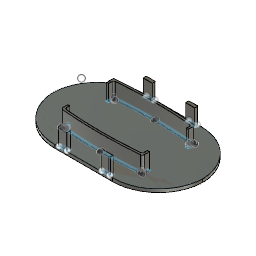
astra-sdr-spacer (Autodesk Fusion 360 design; units mm, degrees)
part number: 2026-04-11-15-15-42-801
Autodesk Fusion 360 part; units mm, degrees
sketch "Sketch1" plane through (0, 0, 0) normal (0, 0, 1) x (1, 0, 0)
  line L0 (70, 0) -> (158, 0)
  line L1 (228, 70) -> (228, 65)
  line L2 (158, 135) -> (70, 135)
  line L3 (0, 65) -> (0, 70)
  arc A0 (70, 135) -> (0, 65) centre (70, 65) ccw
  arc A1 (228, 65) -> (158, 135) centre (158, 65) ccw
  arc A2 (0, 70) -> (70, 0) centre (70, 70) ccw
  arc A3 (158, 0) -> (228, 70) centre (158, 70) ccw
  point P0 (228, 0)
  point P1 (0, 135)
  dimension "d1" = 135
  dimension "d2" = 228
  dimension "d3" = 70
  dimension "d4" = 70
  dimension "d5" = 70
  dimension "d6" = 70
  constraint horizontal L0
  constraint vertical L1
  constraint horizontal L2
  constraint vertical L3
  constraint coincident P1 L2
  constraint coincident P1 L3
  constraint tangent L2 A0
  constraint tangent L3 A0
  constraint tangent L1 A1
  constraint tangent L2 A1
  constraint coincident origin L0
  constraint coincident origin L3
  constraint tangent L0 A2
  constraint tangent L3 A2
  constraint coincident P0 L0
  constraint coincident P0 L1
  constraint tangent L0 A3
  constraint tangent L1 A3
  measures "d1" distance of origin P1
  measures "d2" distance of origin P0
  measures "d3" radius of A0
  measures "d4" radius of A1
  measures "d5" radius of A2
  measures "d6" radius of A3
extrude "Extrude1" add sketch "Sketch1" along normal blind 5 contours L0 L2 A0 A1 A2 A3
sketch "Sketch2" plane through (0, 0, 5) normal (0, 0, 1) x (-1, 0, 0)
  arc A0 (-158, 0) -> (-227.9553, -67.5) centre (-158, -70) ccw
  arc A1 (-227.9553, -67.5) -> (-158, -135) centre (-158, -65) ccw
  line L0 (-158, -135) -> (-70, -135)
  arc A2 (-70, -135) -> (-0.0447, -67.5) centre (-70, -65) ccw
  arc A3 (-0.0447, -67.5) -> (-70, 0) centre (-70, -70) ccw
  line L1 (-70, 0) -> (-158, 0)
  line L2 (-75.5447, -135.011) -> (-87.5447, -135.011)
  line L3 (-88.5447, -134.011) -> (-88.5447, -130.011)
  line L4 (-88.5447, -130.011) -> (-74.5447, -130.011)
  line L5 (-74.5447, -130.011) -> (-74.5447, -134.011)
  line L6 (-152.4553, -134.8199) -> (-140.4553, -134.8199)
  line L7 (-139.4553, -133.8199) -> (-139.4553, -129.8199)
  line L8 (-139.4553, -129.8199) -> (-153.4553, -129.8199)
  line L9 (-153.4553, -129.8199) -> (-153.4553, -133.8199)
  arc A4 (-75.5447, -135.011) -> (-74.5447, -134.011) centre (-75.5447, -134.011) ccw
  arc A5 (-88.5447, -134.011) -> (-87.5447, -135.011) centre (-87.5447, -134.011) ccw
  arc A6 (-140.4553, -134.8199) -> (-139.4553, -133.8199) centre (-140.4553, -133.8199) ccw
  arc A7 (-153.4553, -133.8199) -> (-152.4553, -134.8199) centre (-152.4553, -133.8199) ccw
  line L10 (-152.4553, 0) -> (-140.4553, 0)
  line L11 (-139.1553, -1.3) -> (-139.1553, -5)
  line L12 (-139.1553, -5) -> (-153.7553, -5)
  line L13 (-153.7553, -5) -> (-153.7553, -1.3)
  line L14 (-75.5447, 0) -> (-87.5447, 0)
  line L15 (-88.8447, -1.3) -> (-88.8447, -5)
  line L16 (-88.8447, -5) -> (-74.2447, -5)
  line L17 (-74.2447, -5) -> (-74.2447, -1.3)
  arc A8 (-152.4553, 0) -> (-153.7553, -1.3) centre (-152.4553, -1.3) ccw
  arc A9 (-139.1553, -1.3) -> (-140.4553, 0) centre (-140.4553, -1.3) ccw
  arc A10 (-87.5447, 0) -> (-88.8447, -1.3) centre (-87.5447, -1.3) ccw
  arc A11 (-74.2447, -1.3) -> (-75.5447, 0) centre (-75.5447, -1.3) ccw
  dimension "d9" = 1
  dimension "d10" = 1.3
  dimension "d90" = 75.5
  dimension "d91" = 75.5
  dimension "d92" = 75.5
  dimension "d93" = 75.5
  dimension "d94" = 12
  dimension "d95" = 12
  dimension "d96" = 12
  dimension "d97" = 12
  constraint horizontal L2
  constraint vertical L3
  constraint horizontal L4
  constraint vertical L5
  constraint horizontal L6
  constraint vertical L7
  constraint horizontal L8
  constraint vertical L9
  constraint tangent L2 A4
  constraint tangent L5 A4
  constraint tangent L2 A5
  constraint tangent L3 A5
  constraint equal A4 A5
  constraint tangent L6 A6
  constraint tangent L7 A6
  constraint equal A4 A6
  constraint tangent L6 A7
  constraint tangent L9 A7
  constraint equal A4 A7
  constraint horizontal L10
  constraint vertical L11
  constraint horizontal L12
  constraint vertical L13
  constraint horizontal L14
  constraint vertical L15
  constraint horizontal L16
  constraint vertical L17
  constraint tangent L10 A8
  constraint tangent L13 A8
  constraint tangent L10 A9
  constraint tangent L11 A9
  constraint equal A8 A9
  constraint tangent L14 A10
  constraint tangent L15 A10
  constraint equal A8 A10
  constraint tangent L14 A11
  constraint tangent L17 A11
  constraint equal A8 A11
  measures "d9" radius of A4
  measures "d10" radius of A8
  measures "d90" horizontal distance of A2.end A11.centre
  measures "d91" horizontal distance of A2.end A4.centre
  measures "d92" horizontal distance of A0.end A7.centre
  measures "d93" horizontal distance of A0.end A8.centre
  measures "d94" distance of A6.centre A7.centre
  measures "d95" distance of A8.centre A9.centre
  measures "d96" distance of A4.centre A5.centre
  measures "d97" distance of A10.centre A11.centre
sketch "Sketch3" plane through (0, 0, 5) normal (0, 0, 1) x (-1, 0, 0)
  arc A0 (-158, 0) -> (-227.9553, -67.5) centre (-158, -70) ccw
  arc A1 (-227.9553, -67.5) -> (-158, -135) centre (-158, -65) ccw
  arc A2 (-70, -135) -> (-0.0447, -67.5) centre (-70, -65) ccw
  arc A3 (-0.0447, -67.5) -> (-70, 0) centre (-70, -70) ccw
  line L0 (-70, 0) -> (-158, 0)
  line L1 (-3.1146, -107.5) -> (-3.1146, -107.5692)
  line L2 (-52.0447, -107.5) -> (-52.1045, -107.5)
  line L3 (-54.9911, -97) -> (-52.0447, -97)
  line L4 (-52.0447, -97) -> (-52.0447, -107.5)
  line L5 (-55.0284, -102.2243) -> (-54.9911, -97)
  line L6 (-176.0447, -104.7369) -> (-176.0447, -97)
  line L7 (-176.0447, -97) -> (-172.9902, -97)
  line L8 (-172.9902, -97) -> (-173.0279, -102.1911)
  line L9 (-52.0447, -30.2628) -> (-52.0447, -38)
  line L10 (-55.0447, -32.7922) -> (-55.0447, -38)
  line L11 (-52.0447, -38) -> (-55.0447, -38)
  line L12 (-176.0447, -30.2628) -> (-176.0447, -38)
  line L13 (-173.0447, -32.7922) -> (-173.0447, -38)
  line L14 (-173.0447, -38) -> (-176.0447, -38)
  spline S0 degree 5 poles (-57.3156, -104.6973) (-59.2214, -104.8601) (-63.4872, -105.2111) (-70.113, -105.71) (-79.0988, -106.2872) (-90.4447, -106.8349) (-102.2447, -107.1892) (-114.0447, -107.3105) (-125.8447, -107.1892) (-137.6447, -106.8349) (-148.9838, -106.2875) (-157.963, -105.7109) (-164.5822, -105.2126) (-168.8414, -104.8623) (-170.7406, -104.7002) knots 0.019245 0.019245 0.019245 0.019245 0.019245 0.019245 0.1 0.2 0.3 0.4 0.5 0.6 0.7 0.8 0.9 0.980474 0.980474 0.980474 0.980474 0.980474 0.980474
  spline S1 degree 5 poles (-52.1045, -107.5) (-54.5997, -107.7043) (-59.5816, -108.0956) (-67.0292, -108.6301) (-76.908, -109.2365) (-89.1665, -109.8054) (-101.3317, -110.1679) (-113.4052, -110.3072) (-125.3989, -110.2134) (-137.3431, -109.8956) (-149.2775, -109.3713) (-158.8488, -108.801) (-166.055, -108.2942) (-170.8733, -107.9219) (-173.2861, -107.7271) knots 0 0 0 0 0 0 0.1 0.2 0.3 0.4 0.5 0.6 0.7 0.8 0.9 1 1 1 1 1 1
  spline S2 degree 5 poles (-57.332, -30.3013) (-59.2345, -30.1388) (-63.497, -29.7881) (-70.1196, -29.2896) (-79.1021, -28.7127) (-90.4447, -28.1651) (-102.2447, -27.8108) (-114.0447, -27.6895) (-125.8447, -27.8108) (-137.6447, -28.1651) (-148.9872, -28.7127) (-157.9697, -29.2896) (-164.5923, -29.7881) (-168.8548, -30.1388) (-170.7574, -30.3013) knots 0.019384 0.019384 0.019384 0.019384 0.019384 0.019384 0.1 0.2 0.3 0.4 0.5 0.6 0.7 0.8 0.9 0.980616 0.980616 0.980616 0.980616 0.980616 0.980616
  spline S3 degree 5 poles (-54.8029, -27.2725) (-56.7313, -27.1166) (-61.1396, -26.7729) (-68.028, -26.2809) (-77.3963, -25.7094) (-89.2447, -25.1651) (-101.6447, -24.8108) (-114.0447, -24.6895) (-126.4447, -24.8108) (-138.8447, -25.1651) (-150.693, -25.7094) (-160.0613, -26.2809) (-166.9497, -26.7729) (-171.358, -27.1166) (-173.2864, -27.2725) knots 0.022244 0.022244 0.022244 0.022244 0.022244 0.022244 0.1 0.2 0.3 0.4 0.5 0.6 0.7 0.8 0.9 0.977756 0.977756 0.977756 0.977756 0.977756 0.977756
  arc A4 (-57.3156, -104.6973) -> (-55.0284, -102.2243) centre (-57.5283, -102.2064) ccw
  arc A5 (-173.0279, -102.1911) -> (-170.7406, -104.7002) centre (-170.528, -102.2092) ccw
  arc A6 (-170.7574, -30.3013) -> (-173.0447, -32.7922) centre (-170.5447, -32.7922) ccw
  arc A7 (-55.0447, -32.7922) -> (-57.332, -30.3013) centre (-57.5447, -32.7922) ccw
  arc A8 (-173.2864, -27.2725) -> (-176.0447, -30.2628) centre (-173.0447, -30.2628) ccw
  arc A9 (-52.0447, -30.2628) -> (-54.8029, -27.2725) centre (-55.0447, -30.2628) ccw
  arc A10 (-176.0447, -104.7369) -> (-173.2861, -107.7271) centre (-173.0447, -104.7369) ccw
  point P0 (-55.0447, -104.5)
  point P1 (-173.0447, -104.5)
  point P2 (-176.0447, -107.5)
  point P3 (-55.0447, -30.5)
  point P4 (-173.0447, -30.5)
  point P5 (-176.0447, -27.5)
  point P6 (-52.0447, -27.5)
  point P7 (-114.0447, -107.25)
  point P8 (-114.0447, -110.25)
  point P9 (-114.0447, -27.75)
  point P10 (-114.0447, -24.75)
  dimension "d123" = 118
  dimension "d125" = 118
  dimension "d129" = 3
  dimension "d130" = 3
  dimension "d131" = 3
  dimension "d132" = 3
  dimension "d133" = 3
  dimension "d134" = 7.5
  dimension "d135" = 7.5
  dimension "d136" = 7.5
  dimension "d137" = 7.5
  dimension "d142" = 3
  dimension "d149" = 3
  dimension "d151" = 2.5
  dimension "d152" = 2.5
  dimension "d153" = 2.5
  dimension "d154" = 2.5
  dimension "d155" = 3
  dimension "d156" = 3
  dimension "d157" = 3
  constraint vertical L1
  constraint horizontal L2
  constraint horizontal L3
  constraint vertical L4
  constraint perpendicular L6 L7
  constraint perpendicular L12 L14
  constraint vertical L6
  constraint coincident P0 L5
  constraint tangent L5 A4
  constraint tangent S0 A4
  constraint coincident P1 L8
  constraint tangent L8 A5
  constraint tangent S0 A5
  constraint coincident P4 L13
  constraint tangent L13 A6
  constraint tangent S2 A6
  constraint coincident P3 L10
  constraint tangent L10 A7
  constraint tangent S2 A7
  constraint coincident P5 L12
  constraint tangent L12 A8
  constraint tangent S3 A8
  constraint coincident P6 L9
  constraint tangent L9 A9
  constraint tangent S3 A9
  constraint coincident P2 L6
  constraint tangent L6 A10
  constraint tangent S1 A10
  measures "d123" distance of P0 P1
  measures "d125" distance of P3 P4
  measures "d129" vertical distance of P4 P5
  measures "d130" horizontal distance of P0 L2.start
  measures "d131" horizontal distance of P1 P2
  measures "d132" horizontal distance of P4 P5
  measures "d133" horizontal distance of P3 P6
  measures "d134" vertical distance of P0 L3.end
  measures "d135" vertical distance of P1 L6.end
  measures "d136" vertical distance of P3 L9.end
  measures "d137" vertical distance of P4 L12.end
  measures "d142" vertical distance of P7 P8
  measures "d149" distance of P9 P10
  measures "d151" radius of A4
  measures "d152" radius of A5
  measures "d153" radius of A6
  measures "d154" radius of A7
  measures "d155" radius of A8
  measures "d156" radius of A9
  measures "d157" radius of A10
extrude "Extrude13" add sketch "Sketch2" along normal blind 25 contours L1 L10 L11 L12 L13 A8 A9 | L0 L3 L4 L5 A4 A5 | L1 L14 L15 L16 L17 A10 A11 | L6 L7 L8 L9 A6 A7
extrude "Extrude14" add sketch "Sketch3" along normal blind 24.5 contours L2 L3 L4 L5 L6 L7 L8 S0 S1 A4 A5 A10
extrude "Extrude15" add sketch "Sketch3" along normal blind 24.5 contours L9 L10 L11 L12 L13 L14 S2 S3 A6 A7 A8 A9
named bodies: "astra-sdr-spacer"
